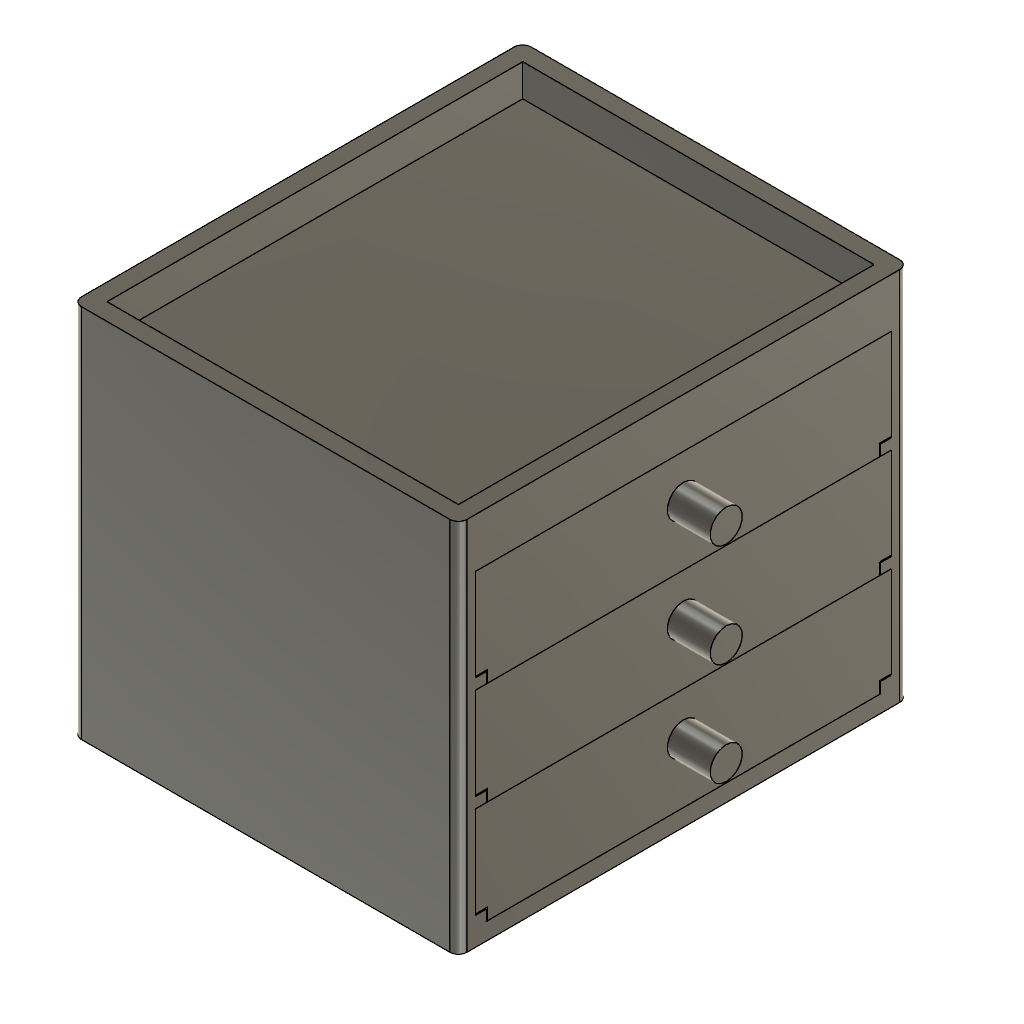
Storage-Box-Source (Autodesk Fusion 360 design; units mm, degrees)
Autodesk Fusion 360 part; units mm, degrees
box "BoxPrimitive1" add length 210 width 180 height 160 placed x (0, 1, 0) y (-1, 0, 0) z (0, 0, 1) at (180, 0, 0) makes body 1
sketch "Sketch3" plane through (180, 0, 0) normal (1, 0, 0) x (0, 1, 0)
  line L0 (0, 160) -> (8, 160)
  line L1 (8, 160) -> (8, 152)
  line L2 (8, 152) -> (0, 152)
  line L3 (0, 152) -> (0, 160)
  line L4 (210, 160) -> (202, 160)
  line L5 (202, 160) -> (202, 152)
  line L6 (202, 152) -> (210, 152)
  line L7 (210, 152) -> (210, 160)
  dimension "d12" = 8
  dimension "d13" = 8
  dimension "d14" = 8
  dimension "d15" = 8
  constraint horizontal L0
  constraint vertical L1
  constraint horizontal L2
  constraint vertical L3
  constraint horizontal L4
  constraint vertical L5
  constraint horizontal L6
  constraint vertical L7
  measures "d12" distance of L0.start L0.end
  measures "d13" distance of L0.start L2.end
  measures "d14" distance of L4.start L4.end
  measures "d15" distance of L4.start L6.end
box "BoxPrimitive2" cut length 42 width 194 height -178 placed x (0, 0, 1) y (0, -1, 0) z (1, 0, 0) at (180, 202, 110) bodies 1
sketch "Sketch5" plane through (180, 0, 0) normal (1, 0, 0) x (0, 1, 0)
  line L0 (0, 0) -> (8, 0)
  line L1 (8, 0) -> (8, 8)
  line L2 (8, 8) -> (0, 8)
  line L3 (0, 8) -> (0, 0)
  line L4 (210, 0) -> (202, 0)
  line L5 (202, 0) -> (202, 8)
  line L6 (202, 8) -> (210, 8)
  line L7 (210, 8) -> (210, 0)
  dimension "d23" = 8
  dimension "d24" = 8
  dimension "d25" = 8
  dimension "d26" = 8
  constraint horizontal L0
  constraint vertical L1
  constraint horizontal L2
  constraint vertical L3
  constraint coincident L0.start L3.end
  constraint horizontal L4
  constraint vertical L5
  constraint horizontal L6
  constraint vertical L7
  measures "d23" distance of L0.start L0.end
  measures "d24" distance of L0.start L2.end
  measures "d25" distance of L4.start L4.end
  measures "d26" distance of L4.start L6.end
box "BoxPrimitive3" cut length 120 width 194 height -178 placed x (0, 0, 1) y (0, -1, 0) z (1, 0, 0) at (180, 202, 8) bodies 1
sketch "Sketch7" plane through (0, 0, 160) normal (0, 0, 1) x (-1, 0, 0)
  line L0 (-180, -210) -> (0, -210)
  line L1 (0, -210) -> (0, 0)
  line L2 (0, 0) -> (-180, 0)
  line L3 (-180, 0) -> (-180, -210)
  line L4 (0, 0) -> (-8, 0)
  line L5 (-8, 0) -> (-8, -8)
  line L6 (-8, -8) -> (0, -8)
  line L7 (0, -8) -> (0, 0)
  line L8 (-180, -210) -> (-172, -210)
  line L9 (-172, -210) -> (-172, -202)
  line L10 (-172, -202) -> (-180, -202)
  line L11 (-180, -202) -> (-180, -210)
  dimension "d34" = 8
  dimension "d35" = 8
  dimension "d36" = 8
  dimension "d37" = 8
  constraint horizontal L4
  constraint vertical L5
  constraint horizontal L6
  constraint vertical L7
  constraint coincident L1.end L2.start
  constraint horizontal L8
  constraint vertical L9
  constraint horizontal L10
  constraint vertical L11
  constraint coincident L0.start L3.end
  measures "d34" distance of L1.end L4.end
  measures "d35" distance of L1.end L6.end
  measures "d36" distance of L0.start L8.end
  measures "d37" distance of L0.start L10.end
box "BoxPrimitive4" add length 210 width 180 height 10 placed x (0, 1, 0) y (-1, 0, 0) z (0, 0, 1) at (180, 0, 160) bodies 1
box "BoxPrimitive5" cut length 194 width 164 height -10 placed x (0, 1, 0) y (-1, 0, 0) z (0, 0, 1) at (172, 8, 170) bodies 1
fillet "Fillet1" radius 4 4 edges at (180, 210, 85) (0, 210, 85) (180, 0, 85) (0, 0, 85) on bodies 1
sketch "Sketch15" plane through (0, 0, 152) normal (0, 0, 1) x (-1, 0, 0)
  line L0 (-180, -202) -> (-2, -202)
  line L1 (-2, -202) -> (-2, -8)
  line L2 (-2, -8) -> (-180, -8)
  line L3 (-180, -8) -> (-180, -202)
  line L4 (-2, -202) -> (-4.5, -202)
  line L5 (-4.5, -202) -> (-4.5, -199.5)
  line L6 (-4.5, -199.5) -> (-2, -199.5)
  line L7 (-2, -199.5) -> (-2, -202)
  line L8 (-180, -8) -> (-177.5, -8)
  line L9 (-177.5, -8) -> (-177.5, -10.5)
  line L10 (-177.5, -10.5) -> (-180, -10.5)
  line L11 (-180, -10.5) -> (-180, -8)
  dimension "d88" = 2.5
  dimension "d89" = 2.5
  dimension "d90" = 2.5
  dimension "d91" = 2.5
  constraint horizontal L4
  constraint vertical L5
  constraint horizontal L6
  constraint vertical L7
  constraint coincident L0.end L1.start
  constraint horizontal L8
  constraint vertical L9
  constraint horizontal L10
  constraint vertical L11
  constraint coincident L2.end L3.start
  measures "d88" distance of L0.end L4.end
  measures "d89" distance of L0.end L6.end
  measures "d90" distance of L2.end L8.end
  measures "d91" distance of L2.end L10.end
extrude "Extrude1" add 1 faces at (2.6667, 72.6667, 170) along direction (0, 0, 1) blind 5 on bodies 1 bodies 1
sketch "Sketch18" plane through (0, 0, 152) normal (0, 0, 1) x (1, 0, 0)
sketch "Sketch19" plane through (180, 0, 0) normal (1, 0, 0) x (0, 1, 0)
  line L0 (4, 175) -> (4, 0)
  line L1 (4, 0) -> (206, 0)
  line L2 (206, 0) -> (206, 175)
  line L3 (206, 175) -> (4, 175)
  line L4 (202, 152) -> (202, 8)
  line L5 (202, 8) -> (8, 8)
  line L6 (8, 8) -> (8, 152)
  line L7 (8, 152) -> (202, 152)
  line L8 (8, 152) -> (202, 152)
  line L9 (202, 152) -> (202, 104)
  line L10 (202, 104) -> (8, 104)
  line L11 (8, 104) -> (8, 152)
  line L12 (8, 104) -> (202, 104)
  line L13 (202, 104) -> (202, 56)
  line L14 (202, 56) -> (8, 56)
  line L15 (8, 56) -> (8, 104)
  line L16 (8, 56) -> (202, 56)
  line L17 (202, 56) -> (202, 8)
  line L18 (202, 8) -> (8, 8)
  line L19 (8, 8) -> (8, 56)
  dimension "d99" = 194
  dimension "d100" = 48
  dimension "d101" = 194
  dimension "d102" = 48
  dimension "d103" = 194
  dimension "d104" = 48
  constraint horizontal L8
  constraint vertical L9
  constraint horizontal L10
  constraint vertical L11
  constraint coincident L6.end L7.start
  constraint horizontal L12
  constraint vertical L13
  constraint horizontal L14
  constraint vertical L15
  constraint horizontal L16
  constraint vertical L17
  constraint horizontal L18
  constraint vertical L19
  measures "d99" distance of L6.end L4.start
  measures "d100" distance of L6.end L10.end
  measures "d101" distance of L10.end L9.end
  measures "d102" distance of L10.end L14.end
  measures "d103" distance of L14.end L13.end
  measures "d104" distance of L14.end L5.end
box "BoxPrimitive11" add length 5 width 5 height -178 placed x (0, 0, 1) y (0, -1, 0) z (1, 0, 0) at (180, 13, 104) bodies 1
box "BoxPrimitive12" add length 5 width 5 height -178 placed x (0, 0, -1) y (0, 1, 0) z (1, 0, 0) at (180, 197, 109) bodies 1
box "BoxPrimitive13" add length 5 width 5 height -178 placed x (0, 0, 1) y (0, -1, 0) z (1, 0, 0) at (180, 13, 56) bodies 1
box "BoxPrimitive14" add length 5 width 5 height -178 placed x (0, 0, -1) y (0, 1, 0) z (1, 0, 0) at (180, 197, 61) bodies 1
box "BoxPrimitive15" add length 5 width 5 height -178 placed x (0, 0, 1) y (0, -1, 0) z (1, 0, 0) at (180, 13, 8) bodies 1
box "BoxPrimitive16" add length 5 width 5 height -178 placed x (0, 0, -1) y (0, 1, 0) z (1, 0, 0) at (180, 197, 13) bodies 1
box "BoxPrimitive17" add length 48 width 194 height -178 placed x (0, 0, 1) y (0, -1, 0) z (1, 0, 0) at (180, 202, 104) separate body makes body 2
box "BoxPrimitive18" cut length 5.5 width 5.5 height -211 placed x (0, 0, 1) y (0, -1, 0) z (1, 0, 0) at (180, 13.5, 104) bodies 2
box "BoxPrimitive19" cut length 5.5 width 5.5 height -227 placed x (0, 0, -1) y (0, 1, 0) z (1, 0, 0) at (180, 196.5, 109.5) bodies 2
box "BoxPrimitive20" cut length 179 width 174 height -45.5 placed x (0, 1, 0) y (-1, 0, 0) z (0, 0, 1) at (178, 15.5, 152) bodies 2
sketch "Sketch32" plane through (0, 0, 152) normal (0, 0, 1) x (-1, 0, 0)
  line L0 (-4, -15.5) -> (-5, -15.5)
  line L1 (-5, -15.5) -> (-5, -98.5)
  line L2 (-5, -98.5) -> (-4, -98.5)
  line L3 (-4, -98.5) -> (-4, -15.5)
  line L4 (-4, -194.5) -> (-5, -194.5)
  line L5 (-5, -194.5) -> (-5, -111.5)
  line L6 (-5, -111.5) -> (-4, -111.5)
  line L7 (-4, -111.5) -> (-4, -194.5)
  line L8 (-4, -194.5) -> (-178, -194.5)
  line L9 (-178, -194.5) -> (-177, -194.5)
  line L10 (-177, -194.5) -> (-177, -111.5)
  line L11 (-177, -111.5) -> (-178, -111.5)
  line L12 (-178, -111.5) -> (-178, -194.5)
  line L13 (-178, -15.5) -> (-177, -15.5)
  line L14 (-177, -15.5) -> (-177, -98.5)
  line L15 (-177, -98.5) -> (-178, -98.5)
  line L16 (-178, -98.5) -> (-178, -15.5)
  dimension "d179" = 1
  dimension "d180" = 83
  dimension "d181" = 1
  dimension "d182" = 83
  dimension "d183" = 1
  dimension "d184" = 83
  dimension "d185" = 1
  dimension "d186" = 83
  constraint horizontal L0
  constraint vertical L1
  constraint horizontal L2
  constraint vertical L3
  constraint horizontal L4
  constraint vertical L5
  constraint horizontal L6
  constraint vertical L7
  constraint coincident L4.start L8
  constraint horizontal L9
  constraint vertical L10
  constraint horizontal L11
  constraint vertical L12
  constraint coincident L8.end L9.start
  constraint horizontal L13
  constraint vertical L14
  constraint horizontal L15
  constraint vertical L16
  measures "d179" distance of L0.start L0.end
  measures "d180" distance of L0.start L2.end
  measures "d181" distance of L4.start L4.end
  measures "d182" distance of L4.start L6.end
  measures "d183" distance of L8.end L9.end
  measures "d184" distance of L8.end L11.end
  measures "d185" distance of L13.start L13.end
  measures "d186" distance of L13.start L15.end
box "BoxPrimitive21" add length 13 width 7 height -45.5 placed x (0, 1, 0) y (-1, 0, 0) z (0, 0, 1) at (11, 98.5, 152) bodies 2
sketch "Sketch34" plane through (0, 0, 152) normal (0, 0, 1) x (-1, 0, 0)
  line L0 (-11, -98.5) -> (-10, -98.5)
  line L1 (-10, -98.5) -> (-10, -102.35)
  line L2 (-10, -102.35) -> (-11, -102.35)
  line L3 (-11, -102.35) -> (-11, -98.5)
  line L4 (-11, -111.5) -> (-10, -111.5)
  line L5 (-10, -111.5) -> (-10, -107.65)
  line L6 (-10, -107.65) -> (-11, -107.65)
  line L7 (-11, -107.65) -> (-11, -111.5)
  line L8 (-11, -107.65) -> (-10, -107.65)
  line L9 (-10, -107.65) -> (-10, -106.15)
  line L10 (-10, -106.15) -> (-11, -106.15)
  line L11 (-11, -106.15) -> (-11, -107.65)
  line L12 (-11, -106.15) -> (-10, -106.15)
  line L13 (-10, -106.15) -> (-10, -103.85)
  line L14 (-10, -103.85) -> (-11, -103.85)
  line L15 (-11, -103.85) -> (-11, -106.15)
  dimension "d192" = 1
  dimension "d193" = 3.85
  dimension "d194" = 1
  dimension "d195" = 3.85
  dimension "d196" = 1
  dimension "d197" = 1.5
  dimension "d198" = 1
  dimension "d199" = 2.3
  constraint horizontal L0
  constraint vertical L1
  constraint horizontal L2
  constraint vertical L3
  constraint horizontal L4
  constraint vertical L5
  constraint horizontal L6
  constraint vertical L7
  constraint horizontal L8
  constraint vertical L9
  constraint horizontal L10
  constraint vertical L11
  constraint horizontal L12
  constraint vertical L13
  constraint horizontal L14
  constraint vertical L15
  measures "d192" distance of L0.start L0.end
  measures "d193" distance of L0.start L2.end
  measures "d194" distance of L4.start L4.end
  measures "d195" distance of L4.start L6.end
  measures "d196" distance of L6.end L5.end
  measures "d197" distance of L6.end L10.end
  measures "d198" distance of L10.end L9.end
  measures "d199" distance of L10.end L14.end
box "BoxPrimitive22" cut length 3.85 width 7 height -45.5 placed x (0, -1, 0) y (1, 0, 0) z (0, 0, 1) at (4, 102.35, 152) bodies 2
box "BoxPrimitive23" cut length 3.85 width 7 height -45.5 placed x (0, -1, 0) y (1, 0, 0) z (0, 0, 1) at (4, 111.5, 152) bodies 2
fillet "Fillet2" radius 5 1 edges at (11, 105, 152) on bodies 2
box "BoxPrimitive24" cut length 2.3 width 7 height -45.5 placed x (0, -1, 0) y (1, 0, 0) z (0, 0, 1) at (4, 106.15, 152) bodies 2
sketch "Sketch38" plane through (0, 0, 152) normal (0, 0, 1) x (-1, 0, 0)
  line L0 (-4, -106.15) -> (-6, -106.15)
  line L1 (-6, -106.15) -> (-6, -107.65)
  line L2 (-6, -107.65) -> (-4, -107.65)
  line L3 (-4, -107.65) -> (-4, -194.5)
  line L4 (-4, -194.5) -> (-178, -194.5)
  line L5 (-178, -194.5) -> (-178, -15.5)
  line L6 (-178, -15.5) -> (-4, -15.5)
  line L7 (-4, -15.5) -> (-4, -102.35)
  line L8 (-4, -102.35) -> (-6, -102.35)
  line L9 (-6, -102.35) -> (-6, -103.85)
  line L10 (-6, -103.85) -> (-4, -103.85)
  line L11 (-4, -103.85) -> (-4, -106.15)
  line L12 (-2, -8) -> (-180, -8)
  line L13 (-180, -8) -> (-180, -202)
  line L14 (-180, -202) -> (-2, -202)
  line L15 (-2, -202) -> (-2, -8)
  line L16 (-178, -15.5) -> (-171, -15.5)
  line L17 (-171, -15.5) -> (-171, -101.75)
  line L18 (-171, -101.75) -> (-178, -101.75)
  line L19 (-178, -101.75) -> (-178, -15.5)
  line L20 (-178, -194.5) -> (-171, -194.5)
  line L21 (-171, -194.5) -> (-171, -108.25)
  line L22 (-171, -108.25) -> (-178, -108.25)
  line L23 (-178, -108.25) -> (-178, -194.5)
  dimension "d221" = 7
  dimension "d222" = 86.25
  dimension "d223" = 7
  dimension "d224" = 86.25
  constraint horizontal L16
  constraint vertical L17
  constraint horizontal L18
  constraint vertical L19
  constraint coincident L5.end L6.start
  constraint horizontal L20
  constraint vertical L21
  constraint horizontal L22
  constraint vertical L23
  constraint coincident L4.end L5.start
  measures "d221" distance of L5.end L16.end
  measures "d222" distance of L5.end L18.end
  measures "d223" distance of L4.end L20.end
  measures "d224" distance of L4.end L22.end
box "BoxPrimitive25" add length 6.5 width 7 height -45.5 placed x (0, -1, 0) y (1, 0, 0) z (0, 0, 1) at (171, 108.25, 152) bodies 2
fillet "Fillet3" radius 5 1 edges at (171, 105, 152) on bodies 2
sketch "Sketch40" plane through (0, 0, 152) normal (0, 0, 1) x (-1, 0, 0)
  line L0 (-176, -108.25) -> (-176, -101.75)
  line L1 (-176, -101.75) -> (-178, -101.75)
  line L2 (-178, -101.75) -> (-178, -15.5)
  line L3 (-178, -15.5) -> (-4, -15.5)
  line L4 (-4, -15.5) -> (-4, -102.35)
  line L5 (-4, -102.35) -> (-6, -102.35)
  line L6 (-6, -102.35) -> (-6, -103.85)
  line L7 (-6, -103.85) -> (-4, -103.85)
  line L8 (-4, -103.85) -> (-4, -106.15)
  line L9 (-4, -106.15) -> (-6, -106.15)
  line L10 (-6, -106.15) -> (-6, -107.65)
  line L11 (-6, -107.65) -> (-4, -107.65)
  line L12 (-4, -107.65) -> (-4, -194.5)
  line L13 (-4, -194.5) -> (-178, -194.5)
  line L14 (-178, -194.5) -> (-178, -108.25)
  line L15 (-178, -108.25) -> (-176, -108.25)
  line L16 (-2, -8) -> (-180, -8)
  line L17 (-180, -8) -> (-180, -202)
  line L18 (-180, -202) -> (-2, -202)
  line L19 (-2, -202) -> (-2, -8)
  line L20 (-178, -108.25) -> (-177, -108.25)
  line L21 (-177, -108.25) -> (-177, -106.75)
  line L22 (-177, -106.75) -> (-178, -106.75)
  line L23 (-178, -106.75) -> (-178, -108.25)
  line L24 (-178, -101.75) -> (-177, -101.75)
  line L25 (-177, -101.75) -> (-177, -103.25)
  line L26 (-177, -103.25) -> (-178, -103.25)
  line L27 (-178, -103.25) -> (-178, -101.75)
  dimension "d232" = 1
  dimension "d233" = 1.5
  dimension "d234" = 1
  dimension "d235" = 1.5
  constraint horizontal L20
  constraint vertical L21
  constraint horizontal L22
  constraint vertical L23
  constraint coincident L14.end L15.start
  constraint horizontal L24
  constraint vertical L25
  constraint horizontal L26
  constraint vertical L27
  constraint coincident L1.end L2.start
  measures "d232" distance of L14.end L20.end
  measures "d233" distance of L14.end L22.end
  measures "d234" distance of L1.end L24.end
  measures "d235" distance of L1.end L26.end
extrude "Extrude2" cut 1 faces at (175.6667, 101.75, 135.1667) along direction (0, 1, 0) blind 0.6 on bodies 2 bodies 2
extrude "Extrude3" cut 1 faces at (175.6667, 108.25, 135.1667) along direction (0, -1, 0) blind 0.6 on bodies 2 bodies 2
sketch "Sketch41" plane through (0, 0, 152) normal (0, 0, 1) x (-1, 0, 0)
  line L0 (-2, -8) -> (-180, -8)
  line L1 (-180, -8) -> (-180, -202)
  line L2 (-180, -202) -> (-2, -202)
  line L3 (-2, -202) -> (-2, -8)
  line L4 (-178, -108.25) -> (-178, -107.65)
  line L5 (-178, -107.65) -> (-176, -107.65)
  line L6 (-176, -107.65) -> (-176, -102.35)
  line L7 (-176, -102.35) -> (-178, -102.35)
  line L8 (-178, -102.35) -> (-178, -101.75)
  line L9 (-178, -101.75) -> (-178, -15.5)
  line L10 (-178, -15.5) -> (-4, -15.5)
  line L11 (-4, -15.5) -> (-4, -102.35)
  line L12 (-4, -102.35) -> (-6, -102.35)
  line L13 (-6, -102.35) -> (-6, -103.85)
  line L14 (-6, -103.85) -> (-4, -103.85)
  line L15 (-4, -103.85) -> (-4, -106.15)
  line L16 (-4, -106.15) -> (-6, -106.15)
  line L17 (-6, -106.15) -> (-6, -107.65)
  line L18 (-6, -107.65) -> (-4, -107.65)
  line L19 (-4, -107.65) -> (-4, -194.5)
  line L20 (-4, -194.5) -> (-178, -194.5)
  line L21 (-178, -194.5) -> (-178, -108.25)
  line L22 (-178, -102.35) -> (-177, -102.35)
  line L23 (-177, -102.35) -> (-177, -103.85)
  line L24 (-177, -103.85) -> (-178, -103.85)
  line L25 (-178, -103.85) -> (-178, -102.35)
  line L26 (-178, -107.65) -> (-177, -107.65)
  line L27 (-177, -107.65) -> (-177, -106.15)
  line L28 (-177, -106.15) -> (-178, -106.15)
  line L29 (-178, -106.15) -> (-178, -107.65)
  dimension "d240" = 1
  dimension "d241" = 1.5
  dimension "d242" = 1
  dimension "d243" = 1.5
  constraint horizontal L22
  constraint vertical L23
  constraint horizontal L24
  constraint vertical L25
  constraint coincident L7.end L8.start
  constraint horizontal L26
  constraint vertical L27
  constraint horizontal L28
  constraint vertical L29
  constraint coincident L4.end L5.start
  measures "d240" distance of L7.end L22.end
  measures "d241" distance of L7.end L24.end
  measures "d242" distance of L4.end L26.end
  measures "d243" distance of L4.end L28.end
box "BoxPrimitive26" cut length 2.3 width 7 height -45.5 placed x (0, -1, 0) y (1, 0, 0) z (0, 0, 1) at (171, 106.15, 152) bodies 2
sketch "Sketch43" plane through (180, 0, 0) normal (1, 0, 0) x (0, 1, 0)
  line L0 (196.5, 109.5) -> (202, 109.5)
  line L1 (202, 109.5) -> (202, 152)
  line L2 (202, 152) -> (8, 152)
  line L3 (8, 152) -> (8, 109.5)
  line L4 (8, 109.5) -> (13.5, 109.5)
  line L5 (13.5, 109.5) -> (13.5, 104)
  line L6 (13.5, 104) -> (196.5, 104)
  line L7 (196.5, 104) -> (196.5, 109.5)
  line L8 (8, 152) -> (105, 152)
  line L9 (105, 152) -> (105, 132)
  line L10 (105, 132) -> (8, 132)
  line L11 (8, 132) -> (8, 152)
  dimension "d251" = 97
  dimension "d252" = 20
  constraint horizontal L8
  constraint vertical L9
  constraint horizontal L10
  constraint vertical L11
  constraint coincident L2.end L3.start
  measures "d251" distance of L2.end L8.end
  measures "d252" distance of L2.end L10.end
cylinder "CylinderPrimitive1" add diameter 15 height 20 placed x (0, 0, -1) y (0, 1, 0) z (1, 0, 0) at (180, 105, 132) bodies 2
box "BoxPrimitive27" add length 2.3 width 174 height 45.5 placed x (0, -1, 0) y (1, 0, 0) z (0, 0, 1) at (0, -50, 0) separate body makes body 3
copy_body "CopyPasteBodies6" bodies 2 makes body 4
move_body "Move6" bodies 4 to x (1, 0, 0) y (0, 1, 0) z (0, 0, 1) at (0, 0, -48)
copy_body "CopyPasteBodies7" bodies 4 makes body 5
move_body "Move7" bodies 5 to x (1, 0, 0) y (0, 1, 0) z (0, 0, 1) at (0, 0, -48)
move_body "Move8" bodies 3 to x (1, 0, 0) y (0, 1, 0) z (0, 0, 1) at (4, 156.1, 106)
copy_body "CopyPasteBodies8" bodies 3 makes body 6
move_body "Move9" bodies 6 to x (1, 0, 0) y (0, 1, 0) z (0, 0, 1) at (0, 0, -47.5)
copy_body "CopyPasteBodies9" bodies 6 makes body 7
move_body "Move10" bodies 7 to x (1, 0, 0) y (0, 1, 0) z (0, 0, 1) at (0, 0, -48)
named bodies: "Main Case", "Upper drawer", "Upper Drawer Divider", "Middle Drawer", "Lower Drawer", "Middle Drawer Divider", "Lower Drawer Divider"
